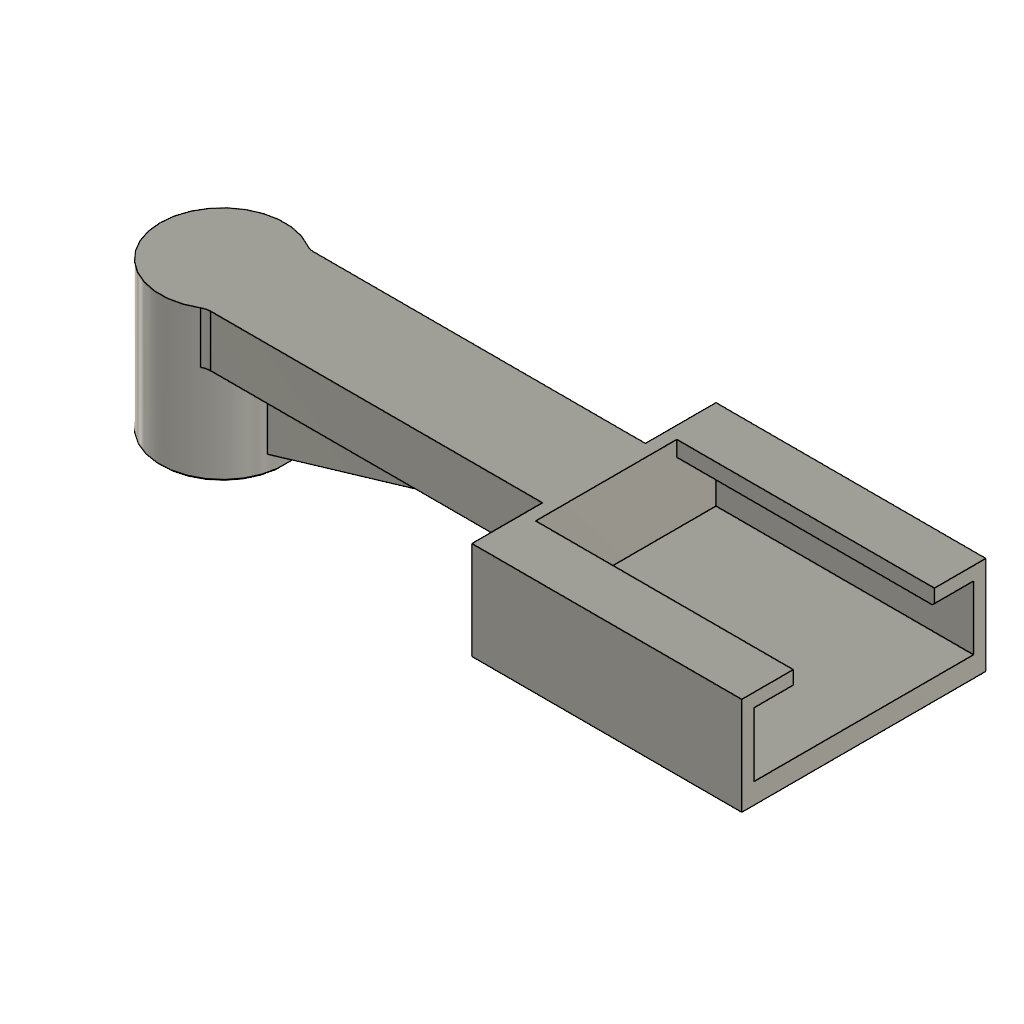
camera_holder_upper_complite (Autodesk Fusion 360 design; units mm, degrees)
part number: 2026-11-14-16-46-26-378
Autodesk Fusion 360 part; units mm, degrees
sketch "01 Socket outer diameter" plane through (0, 0, 0) normal (0, 0, 1) x (1, 0, 0)
  circle A0 centre (0, 0) radius 12.1
  dimension "d53" = 24.2
  measures "d53" diameter of A0
extrude "01 Socket blank and closed top" add sketch "01 Socket outer diameter" along normal blind 29 makes body 1
ref_plane "WorkPlane1" through (0, 0, 19) normal (0, 0, 1) x (1, 0, 0)
sketch "02 Arm - length width and center alignment" plane through (0, 0, 19) normal (0, 0, 1) x (1, 0, 0)
  line L0 (0, -10) -> (72.1, -10)
  line L1 (72.1, -10) -> (72.1, 10)
  line L2 (72.1, 10) -> (0, 10)
  line L3 (0, 10) -> (0, -10)
  dimension "d58" = 72.1
  dimension "d59" = 20
  dimension "d60" = 10
  constraint horizontal L0
  constraint vertical L1
  constraint horizontal L2
  constraint vertical L3
  constraint vertical origin L0.start
  measures "d58" horizontal distance of L0.start L0.end
  measures "d59" vertical distance of L0.start L2.end
  measures "d60" vertical distance of origin L0.start
extrude "02 Horizontal arm" add sketch "02 Arm - length width and center alignment" along normal blind 10 bodies 1
fillet "03 R3 arm to socket stress relief" radius 3 2 edges at (6.8125, -10, 24) (6.8125, 10, 24) on bodies 1
sketch "04 Triangular reinforcing rib - fully dimensioned" plane through (0, 0, 0) normal (0, 1, 0) x (1, 0, 0)
  line L0 (10.1, -19) -> (64.1, -19)
  line L1 (64.1, -19) -> (10.1, -3)
  line L2 (10.1, -3) -> (10.1, -19)
  dimension "d65" = 54
  dimension "d66" = 16
  dimension "d67" = 10.1
  dimension "d68" = 19
  constraint horizontal L0
  constraint vertical L2
  measures "d65" horizontal distance of L0.start L0.end
  measures "d66" vertical distance of L0.start L1.end
  measures "d67" horizontal distance of origin L0.start
  measures "d68" vertical distance of origin L0.start
extrude "04 Central triangular gusset" add sketch "04 Triangular reinforcing rib - fully dimensioned" along normal mid plane 6 bodies 1
ref_plane "WorkPlane2" through (0, 0, 25) normal (0, 0, 1) x (1, 0, 0)
sketch "05 Cradle floor profile" plane through (0, 0, 25) normal (0, 0, 1) x (1, 0, 0)
  line L0 (72.1, -26.2) -> (119.5, -26.2)
  line L1 (119.5, -26.2) -> (119.5, 26.2)
  line L2 (119.5, 26.2) -> (72.1, 26.2)
  line L3 (72.1, 26.2) -> (72.1, -26.2)
  dimension "d73" = 47.4
  dimension "d74" = 52.4
  dimension "d76" = 26.2
  constraint horizontal L0
  constraint vertical L1
  constraint horizontal L2
  constraint vertical L3
  measures "d73" horizontal distance of L0.start L0.end
  measures "d74" vertical distance of L0.start L2.end
  measures "d76" vertical distance of origin L0.start
extrude "05 Cradle floor" add sketch "05 Cradle floor profile" along normal blind 4 bodies 1
sketch "06 Release tongue outer frame profile" plane through (0, 0, 25) normal (0, 0, 1) x (1, 0, 0)
  line L0 (78.1, 26.2) -> (107.5, 26.2)
  line L1 (107.5, 26.2) -> (107.5, 30.2)
  line L2 (107.5, 30.2) -> (78.1, 30.2)
  line L3 (78.1, 30.2) -> (78.1, 26.2)
  dimension "d79" = 29.4
  dimension "d80" = 4
  dimension "d82" = 26.2
  constraint horizontal L0
  constraint vertical L1
  constraint horizontal L2
  constraint vertical L3
  measures "d79" horizontal distance of L0.start L0.end
  measures "d80" vertical distance of L0.start L2.end
  measures "d82" vertical distance of origin L0.start
extrude "06 Release tongue outer frame" [suppressed]
ref_plane "WorkPlane3" through (0, 0, 29) normal (0, 0, 1) x (1, 0, 0)
sketch "07 Closed side stop profile" plane through (0, 0, 29) normal (0, 0, 1) x (1, 0, 0)
  line L0 (72.1, -26.2) -> (119.5, -26.2)
  line L1 (119.5, -26.2) -> (119.5, -23.8)
  line L2 (119.5, -23.8) -> (72.1, -23.8)
  line L3 (72.1, -23.8) -> (72.1, -26.2)
  dimension "d87" = 47.4
  dimension "d88" = 2.4
  dimension "d90" = 26.2
  constraint horizontal L0
  constraint vertical L1
  constraint horizontal L2
  constraint vertical L3
  measures "d87" horizontal distance of L0.start L0.end
  measures "d88" vertical distance of L0.start L2.end
  measures "d90" vertical distance of origin L0.start
extrude "07 Closed side stop" add sketch "07 Closed side stop profile" along normal blind 15 bodies 1
sketch "08 Rear alignment wall profile" plane through (0, 0, 29) normal (0, 0, 1) x (1, 0, 0)
  line L0 (72.1, -26.2) -> (74.5, -26.2)
  line L1 (74.5, -26.2) -> (74.5, 26.2)
  line L2 (74.5, 26.2) -> (72.1, 26.2)
  line L3 (72.1, 26.2) -> (72.1, -26.2)
  dimension "d93" = 2.4
  dimension "d94" = 52.4
  dimension "d96" = 26.2
  constraint horizontal L0
  constraint vertical L1
  constraint horizontal L2
  constraint vertical L3
  measures "d93" horizontal distance of L0.start L0.end
  measures "d94" vertical distance of L0.start L2.end
  measures "d96" vertical distance of origin L0.start
extrude "08 Rear alignment wall" add sketch "08 Rear alignment wall profile" along normal blind 15 bodies 1
ref_plane "WorkPlane4" through (0, 0, 41) normal (0, 0, 1) x (1, 0, 0)
sketch "09 Rear overhead retaining rail profile" plane through (0, 0, 41) normal (0, 0, 1) x (1, 0, 0)
  line L0 (72.1, -26.2) -> (82.1, -26.2)
  line L1 (82.1, -26.2) -> (82.1, 26.2)
  line L2 (82.1, 26.2) -> (72.1, 26.2)
  line L3 (72.1, 26.2) -> (72.1, -26.2)
  dimension "d101" = 10
  dimension "d102" = 52.4
  dimension "d104" = 26.2
  constraint horizontal L0
  constraint vertical L1
  constraint horizontal L2
  constraint vertical L3
  measures "d101" horizontal distance of L0.start L0.end
  measures "d102" vertical distance of L0.start L2.end
  measures "d104" vertical distance of origin L0.start
extrude "09 Rear overhead retaining rail" add sketch "09 Rear overhead retaining rail profile" along normal blind 3 bodies 1
sketch "10 Front overhead retaining rail - hinge stays exposed profile" plane through (0, 0, 41) normal (0, 0, 1) x (1, 0, 0)
  line L0 (109.5, -26.2) -> (119.5, -26.2)
  line L1 (119.5, -26.2) -> (119.5, 26.2)
  line L2 (119.5, 26.2) -> (109.5, 26.2)
  line L3 (109.5, 26.2) -> (109.5, -26.2)
  dimension "d107" = 10
  dimension "d108" = 52.4
  dimension "d110" = 26.2
  constraint horizontal L0
  constraint vertical L1
  constraint horizontal L2
  constraint vertical L3
  measures "d107" horizontal distance of L0.start L0.end
  measures "d108" vertical distance of L0.start L2.end
  measures "d110" vertical distance of origin L0.start
extrude "10 Front overhead retaining rail - hinge stays exposed" add sketch "10 Front overhead retaining rail - hinge stays exposed profile" along normal blind 3 bodies 1
sketch "11 Tube bore diameter and concentricity" plane through (0, 0, 0) normal (0, 0, 1) x (1, 0, 0)
  circle A0 centre (0, 0) radius 8.1
  dimension "d113" = 16.2
  measures "d113" diameter of A0
extrude "11 Blind socket bore - closed top stop" cut sketch "11 Tube bore diameter and concentricity" along normal blind 25 bodies 1
fillet "12 R3 cradle-to-arm root reinforcement" [suppressed]
sketch "13 Release leaf inside slot profile" plane through (0, 0, 25) normal (0, 0, 1) x (1, 0, 0)
  line L0 (80.5, 22.6) -> (105.1, 22.6)
  line L1 (105.1, 22.6) -> (105.1, 23.8)
  line L2 (105.1, 23.8) -> (80.5, 23.8)
  line L3 (80.5, 23.8) -> (80.5, 22.6)
  dimension "d118" = 24.6
  dimension "d119" = 1.2
  dimension "d121" = 22.6
  constraint horizontal L0
  constraint vertical L1
  constraint horizontal L2
  constraint vertical L3
  measures "d118" horizontal distance of L0.start L0.end
  measures "d119" vertical distance of L0.start L2.end
  measures "d121" vertical distance of origin L0.start
extrude "13 Release leaf inside slot" [suppressed]
sketch "14 Release leaf outside slot profile" plane through (0, 0, 25) normal (0, 0, 1) x (1, 0, 0)
  line L0 (80.5, 27.8) -> (105.1, 27.8)
  line L1 (105.1, 27.8) -> (105.1, 28.4)
  line L2 (105.1, 28.4) -> (80.5, 28.4)
  line L3 (80.5, 28.4) -> (80.5, 27.8)
  dimension "d124" = 24.6
  dimension "d125" = 0.6
  constraint horizontal L0
  constraint vertical L1
  constraint horizontal L2
  constraint vertical L3
  measures "d124" horizontal distance of L0.start L0.end
  measures "d125" vertical distance of L0.start L2.end
extrude "14 Release leaf outside slot" [suppressed]
sketch "15 Release leaf end slot profile" plane through (0, 0, 25) normal (0, 0, 1) x (1, 0, 0)
  line L0 (104.5, 22.6) -> (105.1, 22.6)
  line L1 (105.1, 22.6) -> (105.1, 28.4)
  line L2 (105.1, 28.4) -> (104.5, 28.4)
  line L3 (104.5, 28.4) -> (104.5, 22.6)
  dimension "d130" = 0.6
  dimension "d131" = 5.8
  dimension "d133" = 22.6
  constraint horizontal L0
  constraint vertical L1
  constraint horizontal L2
  constraint vertical L3
  measures "d130" horizontal distance of L0.start L0.end
  measures "d131" vertical distance of L0.start L2.end
  measures "d133" vertical distance of origin L0.start
extrude "15 Release leaf end slot" [suppressed]
sketch "16 Release leaf underside clearance profile" plane through (0, 0, 25) normal (0, 0, 1) x (1, 0, 0)
  line L0 (80.5, 23.8) -> (104.5, 23.8)
  line L1 (104.5, 23.8) -> (104.5, 27.8)
  line L2 (104.5, 27.8) -> (80.5, 27.8)
  line L3 (80.5, 27.8) -> (80.5, 23.8)
  dimension "d136" = 24
  dimension "d137" = 4
  dimension "d139" = 23.8
  constraint horizontal L0
  constraint vertical L1
  constraint horizontal L2
  constraint vertical L3
  measures "d136" horizontal distance of L0.start L0.end
  measures "d137" vertical distance of L0.start L2.end
  measures "d139" vertical distance of origin L0.start
extrude "16 Release leaf underside clearance" [suppressed]
fillet "17 Release leaf root stress relief" [suppressed]
ref_plane "WorkPlane5" through (99.5, 0, 0) normal (1, 0, 0) x (0, 1, 0)
sketch "18 Release catch ramp - side insertion" plane through (99.5, 0, 0) normal (1, 0, 0) x (0, 0, -1)
  line L0 (-29, 23.3) -> (-29, 27.8)
  line L1 (-29, 27.8) -> (-31, 23.3)
  line L2 (-31, 23.3) -> (-29, 23.3)
  dimension "d147" = 4.5
  dimension "d148" = 2
  dimension "d149" = 29
  dimension "d150" = 23.3
  constraint vertical L0
  constraint horizontal L2
  measures "d147" vertical distance of L0.start L0.end
  measures "d148" horizontal distance of L0.start L1.end
  measures "d149" horizontal distance of origin L0.start
  measures "d150" vertical distance of origin L0.start
extrude "18 Side-entry retaining ramp and release catch" [suppressed]
chamfer "19 Bore entry lead-in chamfer" distance 0.8 angle 45 1 edges at (-7.5519, -2.9291, 0) tangent chain off on bodies 1
chamfer "20 Socket outer entry edge break" distance 0.4 angle 45 1 edges at (-11.2812, -4.3755, 0) tangent chain off on bodies 1
chamfer "21 Side insertion rail lead-ins" distance 0.4 angle 45 2 edges at (114.5, 26.2, 41) (78.3, 26.2, 41) tangent chain off on bodies 1
ref_plane "WorkPlane6" through (72.1, 0, 0) normal (1, 0, 0) x (0, 1, 0)
split "22 Isolate front holder at unchanged arm interface" by plane through (72.1, 0, 0) normal (1, 0, 0) bodies 1 makes body 2 at (103.7, 3.3333, 25)
move_body "23 Rotate holder 90 degrees - opening toward arm length" bodies 2 to x (0, -1, 0) y (1, 0, 0) z (0, 0, 1) at (0, 0, 0)
move_body "24 Place forward holder at arm end - parameter linked" bodies 2 to x (1, 0, 0) y (0, 1, 0) z (0, 0, 1) at (98.3, 95.8, -15)
combine "25 Rejoin forward holder - one-piece mount" operation add target body 1 tool bodies 2
fillet "26 R3 lower holder junction - top edges level" radius 3 1 edges at (72.1, 0, 19) on bodies 1
ref_plane "WorkPlane7" through (0, 0, 10) normal (0, 0, 1) x (1, 0, 0)
sketch "27 Closed side wall within existing holder outline" plane through (0, 0, 10) normal (0, 0, 1) x (1, 0, 0)
  line L0 (72.1, -23.7) -> (124.5, -23.7)
  line L1 (124.5, -23.7) -> (124.5, -21.3)
  line L2 (124.5, -21.3) -> (72.1, -21.3)
  line L3 (72.1, -21.3) -> (72.1, -23.7)
  dimension "d168" = 52.4
  dimension "d169" = 2.4
  dimension "d171" = 23.7
  constraint horizontal L0
  constraint vertical L1
  constraint horizontal L2
  constraint vertical L3
  measures "d168" horizontal distance of L0.start L0.end
  measures "d169" vertical distance of L0.start L2.end
  measures "d171" vertical distance of origin L0.start
extrude "27 Close open side wall - forward opening retained" add sketch "27 Closed side wall within existing holder outline" along normal blind 19 bodies 1
equation "tubeDiameter = 16 mm" comment "Measured metal tube diameter"
equation "socketClearance = 0.2 mm" comment "DIAMETRAL clearance; nominal bore = 16.2 mm"
equation "socketWall = 4 mm" comment "Socket radial wall thickness"
equation "socketDepth = 25 mm" comment "Socket mouth to closed stop; lead-in is included in this 25 mm depth"
equation "socketCap = 4 mm" comment "Closed top thickness and tube end stop"
equation "entranceChamfer = 0.8 mm" comment "45 degree bore entrance lead-in"
equation "armLength = 60 mm" comment "Distance from socket outer tangent to near edge of clip plate"
equation "armWidth = 20 mm" comment "Arm width"
equation "armThickness = 10 mm" comment "Arm vertical thickness"
equation "rootFillet = 3 mm" comment "Stress-relieving arm/socket fillets"
equation "ribThickness = 6 mm" comment "Centered triangular gusset width"
equation "ribHeight = 16 mm" comment "Gusset height beneath arm at root"
equation "ribOverlap = 2 mm" comment "Gusset penetration into socket wall; keep less than socketWall"
equation "ribTipSetback = 8 mm" comment "Gusset tip setback from plate root"
equation "edgeChamfer = 0.4 mm" comment "Small handling/assembly edge breaks"
equation "socketID = tubeDiameter + socketClearance" comment "Derived bore diameter"
equation "socketOD = socketID + 2 * socketWall" comment "Derived outside diameter"
equation "mountTop = socketDepth + socketCap" comment "Common planar top: put this face on print bed"
equation "armEnd = socketOD / 2 + armLength" comment "Near edge of mounting plate from tube center"
equation "armBase = mountTop - armThickness" comment "Underside of horizontal arm"
equation "clipWidth = 44 mm" comment "Approximate folding-base width from sci-bots C920 community CAD, not a manufacturer tolerance"
equation "clipThickness = 11 mm" comment "Approximate folded base thickness from community CAD: 10.9 mm"
equation "clipLength = 53 mm" comment "Approximate combined folding-base length from community geometry; hinge remains beyond cradle"
equation "channelWidth = 47.6 mm" comment "Clear internal width, based on published C920 stand opening"
equation "channelHeight = 12 mm" comment "Clear vertical opening, based on published C920 stand opening"
equation "engagement = 45 mm" comment "Length of folded horizontal base supported before the exposed hinge"
equation "railWall = 2.4 mm" comment "Rear wall and closed-side stop thickness"
equation "trayFloor = 4 mm" comment "Cradle floor, including room beneath release tongue"
equation "roofThickness = 3 mm" comment "Overhead retaining strap thickness"
equation "rearOverlap = 10 mm - railWall" comment "Rear retaining strap overlap over folding base"
equation "frontStrapWidth = 10 mm" comment "Front overhead retaining strap length along arm"
equation "latchLength = 24 mm" comment "Release leaf length in floor, parallel to arm"
equation "latchWidth = 4 mm" comment "Release leaf width"
equation "latchThickness = 1.2 mm" comment "Six layers at 0.2 mm; bend down to release"
equation "latchHeight = 2 mm" comment "Retaining catch height; press down before removing webcam sideways"
equation "latchSlot = 0.6 mm" comment "Printed clearance around outside and end of release leaf"
equation "latchInnerSlot = 1.2 mm" comment "Inside relief slot around catch overhang"
equation "latchCatchInset = 0.5 mm" comment "Catch projects this far inside nominal channel edge"
equation "latchHeadLength = 5 mm" comment "Catch length along leaf tip"
equation "latchRootInset = 6 mm" comment "Leaf root offset after rear wall"
equation "latchFrameWall = 1.8 mm" comment "Material outside release leaf relief slot"
equation "trayWidth = channelWidth + 2 * railWall" comment "Overall cradle floor width"
equation "trayLength = railWall + engagement" comment "Overall cradle length; front is open for hinge"
equation "trayEnd = armEnd + trayLength" comment "Cradle forward edge"
equation "trayBase = mountTop - trayFloor" comment "Cradle floor underside datum"
equation "roofBase = mountTop + channelHeight" comment "Retaining strap underside"
equation "latchRoot = armEnd + railWall + latchRootInset" comment "Release leaf root X position"
equation "latchEnd = latchRoot + latchLength" comment "Release leaf tip X position"
equation "latchOuter = channelWidth / 2 + latchWidth" comment "Outer side of release leaf"
equation "latchFrameOuter = latchOuter + latchSlot + latchFrameWall" comment "Outside of release frame"
equation "widthAllowance = channelWidth - clipWidth" comment "Total lateral fit allowance from reference nominal"
equation "heightAllowance = channelHeight - clipThickness" comment "Vertical fit allowance from reference nominal"
equation "d53 = socketOD"
equation "d54 = mountTop"
equation "d56 = armBase"
equation "d58 = armEnd"
equation "d59 = armWidth"
equation "d60 = -( -armWidth / 2 )"
equation "d61 = armThickness"
equation "d64 = rootFillet"
equation "d65 = armEnd - ribTipSetback - ( socketOD / 2 - ribOverlap )"
equation "d66 = ribHeight"
equation "d67 = socketOD / 2 - ribOverlap"
equation "d68 = armBase"
equation "d69 = ribThickness"
equation "d71 = trayBase"
equation "d73 = trayLength"
equation "d74 = trayWidth"
equation "d75 = ( armEnd )"
equation "d76 = -( -trayWidth / 2 )"
equation "d77 = trayFloor"
equation "d79 = latchLength + latchSlot + 2 * railWall"
equation "d80 = latchFrameOuter - trayWidth / 2"
equation "d81 = ( latchRoot - railWall )"
equation "d82 = ( trayWidth / 2 )"
equation "d83 = trayFloor"
equation "d85 = mountTop"
equation "d87 = trayLength"
equation "d88 = railWall"
equation "d89 = ( armEnd )"
equation "d90 = -( -trayWidth / 2 )"
equation "d91 = channelHeight + roofThickness"
equation "d93 = railWall"
equation "d94 = trayWidth"
equation "d95 = ( armEnd )"
equation "d96 = -( -trayWidth / 2 )"
equation "d97 = channelHeight + roofThickness"
equation "d99 = roofBase"
equation "d101 = railWall + rearOverlap"
equation "d102 = trayWidth"
equation "d103 = ( armEnd )"
equation "d104 = -( -trayWidth / 2 )"
equation "d105 = roofThickness"
equation "d107 = frontStrapWidth"
equation "d108 = trayWidth"
equation "d109 = ( trayEnd - frontStrapWidth )"
equation "d110 = -( -trayWidth / 2 )"
equation "d111 = roofThickness"
equation "d113 = socketID"
equation "d114 = socketDepth"
equation "d117 = rootFillet"
equation "d118 = latchLength + latchSlot"
equation "d119 = latchInnerSlot"
equation "d120 = ( latchRoot )"
equation "d121 = ( channelWidth / 2 - latchInnerSlot )"
equation "d122 = trayFloor"
equation "d124 = latchLength + latchSlot"
equation "d125 = latchSlot"
equation "d126 = ( latchRoot )"
equation "d127 = ( latchOuter )"
equation "d128 = trayFloor"
equation "d130 = latchSlot"
equation "d131 = latchWidth + latchInnerSlot + latchSlot"
equation "d132 = ( latchEnd )"
equation "d133 = ( channelWidth / 2 - latchInnerSlot )"
equation "d134 = trayFloor"
equation "d136 = latchLength"
equation "d137 = latchWidth"
equation "d138 = ( latchRoot )"
equation "d139 = ( channelWidth / 2 )"
equation "d140 = trayFloor - latchThickness"
equation "latchRootRadius = 0.6 mm" comment "Small underside root fillet on release tongue"
equation "d144 = latchRootRadius"
equation "d145 = latchEnd - latchHeadLength"
equation "d147 = latchWidth + latchCatchInset"
equation "d148 = latchHeight"
equation "d149 = mountTop"
equation "d150 = channelWidth / 2 - latchCatchInset"
equation "d151 = latchHeadLength"
equation "d153 = entranceChamfer"
equation "d154 = edgeChamfer"
equation "d155 = edgeChamfer"
equation "catchHoldMargin = latchHeight - heightAllowance" comment "Catch height above available lift under rails; keep positive"
equation "latchTravelMargin = trayFloor - latchThickness - latchHeight" comment "Under-leaf space remaining at nominal release movement; keep positive"
equation "d158 = armEnd"
equation "d161 = armEnd + trayWidth / 2"
equation "d162 = armEnd + trayLength / 2"
equation "d163 = -( channelHeight + roofThickness )"
equation "d165 = rootFillet"
equation "d166 = mountTop - channelHeight - roofThickness - trayFloor"
equation "d168 = trayWidth"
equation "d169 = railWall"
equation "d170 = ( armEnd )"
equation "d171 = -( -trayLength / 2 )"
equation "d172 = trayFloor + channelHeight + roofThickness"
named bodies: "Single PLA mount - closed sides and flush forward opening", "Holder orientation tool body"
